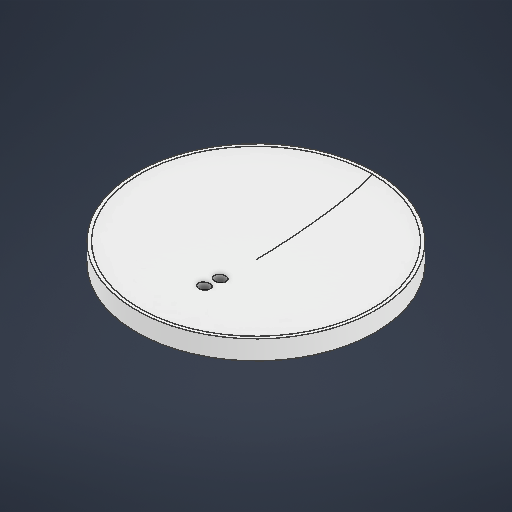
# Autodesk Inventor part: R-1
Saved by Autodesk Inventor 2026.2 (Build 302298010, 298A)
## iProperties
Created: 2026-03-20
Part Number: R-1
Material: ABS 플라스틱
Document SubType Name: Modeling
Designer: work
Density: 1.06 g/cm^3
Appearance: 매끄러움 - 흰색
Mass: 128.685 g
Surface Area: 417.976 cm^2
Volume: 121.401 cm^3
Author: work
Autodesk Inventor part; units mm, degrees
ref_plane "YZ Plane" through (0, 0, 0) normal (1, 0, 0) x (0, 1, 0)
ref_plane "XZ Plane" through (0, 0, 0) normal (0, 1, 0) x (-1, 0, 0)
sketch "스케치1" plane through (0, 0, 0) normal (0, 1, 0) x (-1, 0, 0)
  circle A0 centre (0, 0) radius 2.5
  line L0 (0, 0) -> (0, 10) construction
  circle A1 centre (0, 10) radius 2.5
  line L1 (0, 10) -> (0, 0) construction
  line L2 (-6.25, 10) -> (-6.25, 0)
  line L3 (6.25, 0) -> (6.25, 10)
  arc A2 (6.25, 10) -> (-6.25, 10) centre (0, 10) ccw
  arc A3 (-6.25, 0) -> (6.25, 0) centre (0, 0) ccw
  point P0 (0, 5)
  dimension "d0" = 5
  dimension "d1" = 10
  dimension "d2" = 5
  dimension "d3" = 12.5
  constraints: 10 end point, 4 centre point, 4 point on circle, 4 tangent, 2 coincident, 2 equal length, 2 midpoint, 1 vertical
  measures "d0" diameter of A0
  measures "d1" distance of L0.start L0.end
  measures "d2" diameter of A1
  measures "d3" diameter of A3
extrude "돌출1" add sketch "스케치1" along normal blind 4
sketch "스케치2" plane through (0, 4, 0) normal (0, 1, 0) x (1, 0, 0)
  line L0 (0, 0) -> (0, 22.4)
  circle A0 centre (0, 22.4) radius 75
  circle A1 centre (0, 0) radius 2.5 projected
  circle A2 centre (0, -10) radius 2.5 projected
  dimension "d6" = 22.4
  dimension "d7" = 150
  constraints: 2 end point, 1 centre point, 1 coincident, 1 vertical
  measures "d6" distance of L0.start L0.end
  measures "d7" diameter of A0
extrude "돌출2" add sketch "스케치2" along normal blind 2
sketch "스케치3" plane through (0, 6, -22.4) normal (0, 1, 0) x (1, 0, 0)
  circle A0 centre (0, 0) radius 75 projected
  circle A1 centre (0, -22.4) radius 2.5 projected
  circle A2 centre (0, -32.4) radius 2.5 projected
  arc A3 (6.25, -22.4) -> (-6.25, -22.4) centre (0, -22.4) ccw projected
  circle A4 centre (0, -22.4) radius 3.5
  circle A5 centre (0, -32.4) radius 3.5
  dimension "d10" = 7
  dimension "d11" = 7
  constraints: 2 centre point, 2 coincident
  measures "d10" diameter of A4
  measures "d11" diameter of A5
extrude "돌출3" cut sketch "스케치3" against normal blind 4 contours A4 | A5
fillet "모깎기1" radius 2 4 edges at (0, 4, -6.25) (-6.25, 4, 5) (0, 4, 16.25) (6.25, 4, 5)
ref_plane "작업 평면1" through (0, 0, 0) normal (-1, 0, 0) x (0, 0, 1)
sketch "스케치4" plane through (0, 0, 0) normal (-1, 0, 0) x (0, 0, 1)
  line L0 (52.6, 6) -> (-97.4, 6) projected
  line L1 (-97.4, 6) -> (-97.4, 16)
  line L2 (-22.4, 6) -> (-22.4, 23.0443)
  line L3 (-97.4, 16) -> (-95.4, 16)
  spline S0 degree 3 poles (-95.4, 16) (-88.3052, 11.6062) (-51.5755, 6) (-22.4, 6) knots 0 0 0 0 1 1 1 1
  point P0 (0, 0)
  point P1 (-77.4, 11)
  dimension "d15" = 10
  dimension "d16" = 2
  dimension "d17" = 20
  dimension "d18" = 5
  constraints: 6 end point, 2 horizontal, 2 vertical, 1 midpoint, 3 other
  measures "d15" distance of L0.end L1.end
  measures "d16" distance of L1.end L3.end
  measures "d17" horizontal distance of L0.end point (-77.4, 11)
  measures "d18" vertical distance of L0.end point (-77.4, 11)
revolve "회전1" add sketch "스케치4" angle 360 about axis through (0, 6, -22.4) along (0, 1, 0)
sketch "스케치5" plane through (0, 6, 0) normal (0, -1, 0) x (1, 0, 0)
  circle A0 centre (0, 0) radius 3.5 projected
  circle A1 centre (0, 10) radius 3.5 projected
extrude "돌출4" cut sketch "스케치5" against normal through all
